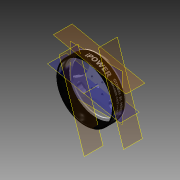
# Autodesk Inventor part: end_bell
Saved by Autodesk Inventor 2013 (Build 170138000, 138)
## iProperties
Created: 2013-09-27
Part Number: end_bell
Material: Generic
Document SubType Name: Modeling
Designer: Hunter
Density: 1 g/cm^3
Author: Hunter
Autodesk Inventor part; units mm, degrees
(part 1 of 2)
ref_plane "YZ Plane" through (0, 0, 0) normal (1, 0, 0) x (0, 1, 0)
ref_plane "XZ Plane" through (0, 0, 0) normal (0, 1, 0) x (-1, 0, 0)
ref_plane "XY Plane" through (0, 0, 0) normal (0, 0, 1) x (1, 0, 0)
sketch "Sketch1" plane through (0, 0, 0) normal (0, 1, 0) x (-1, 0, 0)
  circle A0 centre (0, 0) radius 25
  circle A1 centre (0, 0) radius 1.585
  circle A2 centre (0, 16) radius 4
  circle A3 centre (-13.8564, -8) radius 4
  circle A4 centre (13.8564, -8) radius 4
  line L0 (0, 0) -> (19.669, 0) construction
  line L1 (0, 0) -> (0, 10.3871) construction
  line L2 (-4.2426, -4.2426) -> (4.2426, -4.2426) construction
  line L3 (4.2426, -4.2426) -> (4.2426, 4.2426) construction
  line L4 (4.2426, 4.2426) -> (-4.2426, 4.2426) construction
  line L5 (-4.2426, 4.2426) -> (-4.2426, -4.2426) construction
  circle A5 centre (-4.2426, 4.2426) radius 1
  circle A6 centre (4.2426, 4.2426) radius 1
  circle A7 centre (-4.2426, -4.2426) radius 1
  circle A8 centre (4.2426, -4.2426) radius 1
  line L6 (-4.2426, 4.2426) -> (4.2426, -4.2426) construction
  dimension "d0" = 50
  dimension "d1" = 3.17
  dimension "d2" = 8
  dimension "d3" = 16
  dimension "d6" = 360
  dimension "d10" = 2
  dimension "d11" = 2
  dimension "d12" = 2
  dimension "d13" = 2
  dimension "d86" = 12
  constraints: 14 end point, 9 centre point, 6 coincident, 3 horizontal, 2 parallel, 2 perpendicular, 9 other
  measures "d0" diameter of A0
  measures "d1" diameter of A1
  measures "d2" diameter of A2
  measures "d3" distance of L0.start A2.centre
  measures "d10" diameter of A5
  measures "d11" diameter of A6
  measures "d12" diameter of A7
  measures "d13" diameter of A8
  measures "d86" distance of L6.start L6.end
extrude "Extrusion1" add sketch "Sketch1" along normal blind 15
sketch "Sketch2" plane through (0, 15, 0) normal (0, 1, 0) x (1, 0, 0)
  circle A0 centre (13.8564, 8) radius 4 projected
  circle A1 centre (0, -16) radius 4 projected
  circle A2 centre (0, 0) radius 1.585 projected
  circle A3 centre (0, 0) radius 25 projected
  line L0 (0, 0) -> (46.4699, 0) construction
  circle A4 centre (0, 32.1597) radius 21.3512
  circle A5 centre (-27.8511, -16.0798) radius 21.3512
  circle A6 centre (27.8511, -16.0798) radius 21.3512
  circle A7 centre (0, -16) radius 6.5 construction
  circle A8 centre (13.8564, 8) radius 6.5 construction
  dimension "d19" = 360
  dimension "d21" = 13
  dimension "d22" = 13
  constraints: 5 centre point, 2 coincident, 2 end point, 1 horizontal, 1 tangent, 7 other
  measures "d21" diameter of A7
  measures "d22" diameter of A8
extrude "Extrusion2" cut sketch "Sketch2" against normal blind 4 contours A3 A6 | A3 A6 | A4 A3 | A3 A4 | A5 A3 | A3 A5
chamfer "Chamfer1" distance 4 angle 45 1 edges at (-21.6506, 15, -12.5)
chamfer "Chamfer2" distance 4 angle 45 2 edges at (21.6506, 15, -12.5) (0, 15, 25)
sketch "Sketch3" plane through (0, 0, 0) normal (0, -1, 0) x (1, 0, 0)
  circle A0 centre (-13.8564, -8) radius 4 projected
  circle A1 centre (13.8564, -8) radius 4 projected
  circle A2 centre (0, 16) radius 4 projected
  circle A3 centre (0, 0) radius 1.585 projected
  circle A4 centre (-4.2426, -4.2426) radius 1 projected
  circle A5 centre (4.2426, -4.2426) radius 1 projected
  circle A6 centre (-4.2426, 4.2426) radius 1 projected
  circle A7 centre (4.2426, 4.2426) radius 1 projected
  circle A8 centre (0, 0) radius 25 projected
  circle A9 centre (0, 0) radius 23.7
  dimension "d31" = 1.3
  constraints: 1 centre point, 1 coincident
  measures "d31" radial gap between concentric circles of A8 A9
extrude "Extrusion3" cut sketch "Sketch3" against normal blind 10 contours A9
sketch "Sketch4" plane through (0, 10, 0) normal (0, -1, 0) x (1, 0, 0)
  circle A0 centre (0, 16) radius 4 projected
  circle A1 centre (13.8564, -8) radius 4 projected
  circle A2 centre (-13.8564, -8) radius 4 projected
  circle A3 centre (0, 0) radius 1.585 projected
  circle A4 centre (4.2426, 4.2426) radius 1 projected
  circle A5 centre (-4.2426, 4.2426) radius 1 projected
  circle A6 centre (4.2426, -4.2426) radius 1 projected
  circle A7 centre (-4.2426, -4.2426) radius 1 projected
  circle A8 centre (0, 0) radius 23.7 projected
  circle A9 centre (0, 0) radius 21.7
  dimension "d34" = 43.4
  constraints: 1 centre point, 1 coincident
  measures "d34" diameter of A9
extrude "Extrusion4" cut sketch "Sketch4" against normal blind 1 contours A9
hole "Hole1" at (-4.2426, 15, 4.2426) direction (0, -1, 0) diameter 2.013 end through all thread size "M2.5x0.45" class "6H" standard "ANSI Metric M Profile"
hole "Hole2" at (-4.2426, 15, -4.2426) direction (0, -1, 0) diameter 2.013 end through all thread size "M2.5x0.45" class "6H" standard "ANSI Metric M Profile"
hole "Hole3" at (4.2426, 15, -4.2426) direction (0, -1, 0) diameter 2.013 end through all thread size "M2.5x0.45" class "6H" standard "ANSI Metric M Profile"
hole "Hole4" at (4.2426, 15, 4.2426) direction (0, -1, 0) diameter 2.013 end through all thread size "M2.5x0.45" class "6H" standard "ANSI Metric M Profile"
chamfer "Chamfer3" distance 0.1 angle 45 4 edges at (-4.2426, 15, -5.2491) (-4.2426, 15, 3.2361) (4.2426, 15, 3.2361) (4.2426, 15, -5.2491)
ref_plane "Work Plane1" through (0, 10, 0) normal (0, 1, 0) x (1, 0, 0)
split body "Split1" result two bodies by plane through (0, 10, 0) normal (0, 1, 0) first body at (-7.4399, 11.5, 0.4135)
fillet "Fillet1" radius 0.3 1 edges at (25, 0, 0)
fillet "Fillet2" radius 0.3 1 edges at (-23.7, 0, 0)
ref_plane "Work Plane2" through (0, 0, 0) normal (0.9488702, 0, 0.3156666) x (0, 1, 0)
ref_plane "Work Plane3" through (23.7218, 0, 7.8917) normal (0.9488702, 0, 0.3156666) x (0, 1, 0)
sketch "Sketch5" plane through (23.7218, 0, 7.8917) normal (0.9488702, 0, 0.3156666) x (0, 1, 0)
  line L0 (-5.6648, 40.291) -> (1.694, 40.291)
  line L1 (1.694, 40.291) -> (1.694, -6.6562)
  line L2 (1.694, -6.6562) -> (-5.6648, -6.6562)
  line L3 (-5.6648, -6.6562) -> (-5.6648, 40.291)
  line L4 (7.9505, 10.1086) -> (7.9505, -71.0946) construction
  line L5 (7.9505, -71.0946) -> (-7.0524, -71.0946) construction
  line L6 (-7.0524, -71.0946) -> (-7.0524, 10.1086) construction
  line L7 (-7.0524, 10.1086) -> (7.9505, 10.1086) construction
  spline S0 degree 2 poles (6.0218, 8.2317) (5.9683, 8.363) (5.8662, 8.7828) (5.8662, 8.987) knots 0 0 0 1 2 2 2
  spline S1 degree 2 poles (5.8662, 8.987) (5.8662, 9.4586) (6.4108, 10.0178) (6.91, 10.0178) knots 0 0 0 1 2 2 2
  spline S2 degree 2 poles (6.91, 10.0178) (7.38, 10.0178) (7.9472, 9.4586) (7.9472, 8.9724) knots 0 0 0 1 2 2 2
  spline S3 degree 2 poles (7.9472, 8.9724) (7.9472, 8.7212) (7.8516, 8.4068) (7.7706, 8.2398) knots 0 0 0 1 2 2 2
  line L8 (7.7706, 8.2398) -> (7.3006, 8.2398)
  line L9 (7.3006, 8.2398) -> (7.3006, 8.2852)
  spline S4 degree 2 poles (7.3006, 8.2852) (7.3281, 8.3209) (7.4335, 8.457) (7.4691, 8.5218) knots 0 0 0 1 2 2 2
  spline S5 degree 2 poles (7.4691, 8.5218) (7.5129, 8.5964) (7.5745, 8.7941) (7.5745, 8.9043) knots 0 0 0 1 2 2 2
  spline S6 degree 2 poles (7.5745, 8.9043) (7.5745, 9.0324) (7.4934, 9.2447) (7.4108, 9.3274) knots 0 0 0 1 2 2 2
  spline S7 degree 2 poles (7.4108, 9.3274) (7.3297, 9.4068) (7.0818, 9.4992) (6.9181, 9.4992) knots 0 0 0 1 2 2 2
  spline S8 degree 2 poles (6.9181, 9.4992) (6.568, 9.4992) (6.2341, 9.1475) (6.2341, 8.8444) knots 0 0 0 1 2 2 2
  spline S9 degree 2 poles (6.2341, 8.8444) (6.2341, 8.8168) (6.2374, 8.7455) (6.239, 8.718) knots 0 0 0 1 2 2 2
  line L10 (6.239, 8.718) -> (6.6328, 8.718)
  line L11 (6.6328, 8.718) -> (6.6328, 9.1053)
  line L12 (6.6328, 9.1053) -> (7.0072, 9.1053)
  line L13 (7.0072, 9.1053) -> (7.0072, 8.2317)
  line L14 (7.0072, 8.2317) -> (6.0218, 8.2317)
  line L15 (5.9083, 6.8573) -> (5.9083, 7.9335)
  line L16 (5.9083, 7.9335) -> (6.2568, 7.9335)
  line L17 (6.2568, 7.9335) -> (6.2568, 7.6466)
  line L18 (6.2568, 7.6466) -> (7.5599, 7.6466)
  line L19 (7.5599, 7.6466) -> (7.5599, 7.9335)
  line L20 (7.5599, 7.9335) -> (7.9083, 7.9335)
  line L21 (7.9083, 7.9335) -> (7.9083, 6.8573)
  line L22 (7.9083, 6.8573) -> (7.5599, 6.8573)
  line L23 (7.5599, 6.8573) -> (7.5599, 7.1442)
  line L24 (7.5599, 7.1442) -> (6.2568, 7.1442)
  line L25 (6.2568, 7.1442) -> (6.2568, 6.8573)
  line L26 (6.2568, 6.8573) -> (5.9083, 6.8573)
  line L27 (5.9083, 4.4813) -> (5.9083, 4.9805)
  line L28 (5.9083, 4.9805) -> (7.2341, 4.9805)
  line L29 (7.2341, 4.9805) -> (6.3784, 5.3436)
  line L30 (6.3784, 5.3436) -> (6.3784, 5.6872)
  line L31 (6.3784, 5.6872) -> (7.2341, 6.0502)
  line L32 (7.2341, 6.0502) -> (5.9083, 6.0502)
  line L33 (5.9083, 6.0502) -> (5.9083, 6.5235)
  line L34 (5.9083, 6.5235) -> (7.9083, 6.5235)
  line L35 (7.9083, 6.5235) -> (7.9083, 5.9449)
  line L36 (7.9083, 5.9449) -> (6.9213, 5.5008)
  line L37 (6.9213, 5.5008) -> (7.9083, 5.0599)
  line L38 (7.9083, 5.0599) -> (7.9083, 4.4813)
  line L39 (7.9083, 4.4813) -> (5.9083, 4.4813)
  spline S10 degree 2 poles (6.521, 2.4684) (6.3719, 2.4684) (6.1466, 2.5818) (6.072, 2.6758) knots 0 0 0 1 2 2 2
  spline S11 degree 2 poles (6.072, 2.6758) (5.9829, 2.7893) (5.9083, 3.0583) (5.9083, 3.2674) knots 0 0 0 1 2 2 2
  line L40 (5.9083, 3.2674) -> (5.9083, 4.0664)
  line L41 (5.9083, 4.0664) -> (7.9083, 4.0664)
  line L42 (7.9083, 4.0664) -> (7.9083, 3.3614)
  spline S12 degree 2 poles (7.9083, 3.3614) (7.9083, 3.141) (7.8743, 2.9141) (7.8208, 2.8152) knots 0 0 0 1 2 2 2
  spline S13 degree 2 poles (7.8208, 2.8152) (7.7641, 2.7066) (7.5696, 2.6013) (7.4432, 2.6013) knots 0 0 0 1 2 2 2
  spline S14 degree 2 poles (7.4432, 2.6013) (7.2973, 2.6013) (7.0688, 2.7471) (7.0153, 2.8768) knots 0 0 0 1 2 2 2
  line L43 (7.0153, 2.8768) -> (7.0056, 2.8768)
  spline S15 degree 2 poles (7.0056, 2.8768) (6.9667, 2.6904) (6.7252, 2.4684) (6.521, 2.4684) knots 0 0 0 1 2 2 2
  spline S16 degree 2 poles (6.5291, 2.987) (6.6231, 2.987) (6.7284, 3.0616) (6.756, 3.1361) knots 0 0 0 1 2 2 2
  spline S17 degree 2 poles (6.756, 3.1361) (6.7738, 3.1815) (6.7771, 3.3419) (6.7771, 3.4748) knots 0 0 0 1 2 2 2
  line L44 (6.7771, 3.4748) -> (6.7771, 3.5672)
  line L45 (6.7771, 3.5672) -> (6.273, 3.5672)
  line L46 (6.273, 3.5672) -> (6.273, 3.5397)
  spline S18 degree 2 poles (6.273, 3.5397) (6.273, 3.3452) (6.2779, 3.1961) (6.3119, 3.1183) knots 0 0 0 1 2 2 2
  spline S19 degree 2 poles (6.3119, 3.1183) (6.3427, 3.0502) (6.4562, 2.987) (6.5291, 2.987) knots 0 0 0 1 2 2 2
  spline S20 degree 2 poles (7.3443, 3.1118) (7.3929, 3.1118) (7.4951, 3.162) (7.5177, 3.2139) knots 0 0 0 1 2 2 2
  spline S21 degree 2 poles (7.5177, 3.2139) (7.5404, 3.2625) (7.5437, 3.3987) (7.5437, 3.5332) knots 0 0 0 1 2 2 2
  line L47 (7.5437, 3.5332) -> (7.5437, 3.5672)
  line L48 (7.5437, 3.5672) -> (7.119, 3.5672)
  line L49 (7.119, 3.5672) -> (7.119, 3.504)
  spline S22 degree 2 poles (7.119, 3.504) (7.119, 3.376) (7.1239, 3.2723) (7.1498, 3.2171) knots 0 0 0 1 2 2 2
  spline S23 degree 2 poles (7.1498, 3.2171) (7.179, 3.1572) (7.2779, 3.1118) (7.3443, 3.1118) knots 0 0 0 1 2 2 2
  line L50 (5.9083, 2.3954) -> (7.9083, 1.7196)
  line L51 (7.9083, 1.7196) -> (7.9083, 1.1718)
  line L52 (7.9083, 1.1718) -> (5.9083, 0.4959)
  line L53 (5.9083, 0.4959) -> (5.9083, 1.0129)
  line L54 (5.9083, 1.0129) -> (6.3168, 1.1377)
  line L55 (6.3168, 1.1377) -> (6.3168, 1.7666)
  line L56 (6.3168, 1.7666) -> (5.9083, 1.893)
  line L57 (5.9083, 1.893) -> (5.9083, 2.3954)
  line L58 (6.6798, 1.2479) -> (7.3411, 1.4522)
  line L59 (7.3411, 1.4522) -> (6.6798, 1.658)
  line L60 (6.6798, 1.658) -> (6.6798, 1.2479)
  line L61 (5.9083, -1.0373) -> (5.9083, 0.2966)
  line L62 (5.9083, 0.2966) -> (7.9083, 0.2966)
  line L63 (7.9083, 0.2966) -> (7.9083, -0.2059)
  line L64 (7.9083, -0.2059) -> (6.2892, -0.2059)
  line L65 (6.2892, -0.2059) -> (6.2892, -1.0373)
  line L66 (6.2892, -1.0373) -> (5.9083, -1.0373)
  spline S24 degree 2 poles (6.521, -3.6807) (6.3719, -3.6807) (6.1466, -3.5673) (6.072, -3.4733) knots 0 0 0 1 2 2 2
  spline S25 degree 2 poles (6.072, -3.4733) (5.9829, -3.3598) (5.9083, -3.0908) (5.9083, -2.8817) knots 0 0 0 1 2 2 2
  line L67 (5.9083, -2.8817) -> (5.9083, -2.0827)
  line L68 (5.9083, -2.0827) -> (7.9083, -2.0827)
  line L69 (7.9083, -2.0827) -> (7.9083, -2.7877)
  spline S26 degree 2 poles (7.9083, -2.7877) (7.9083, -3.0081) (7.8743, -3.235) (7.8208, -3.3339) knots 0 0 0 1 2 2 2
  spline S27 degree 2 poles (7.8208, -3.3339) (7.7641, -3.4425) (7.5696, -3.5478) (7.4432, -3.5478) knots 0 0 0 1 2 2 2
  spline S28 degree 2 poles (7.4432, -3.5478) (7.2973, -3.5478) (7.0688, -3.402) (7.0153, -3.2723) knots 0 0 0 1 2 2 2
  line L70 (7.0153, -3.2723) -> (7.0056, -3.2723)
  spline S29 degree 2 poles (7.0056, -3.2723) (6.9667, -3.4587) (6.7252, -3.6807) (6.521, -3.6807) knots 0 0 0 1 2 2 2
  spline S30 degree 2 poles (6.5291, -3.1621) (6.6231, -3.1621) (6.7284, -3.0876) (6.756, -3.013) knots 0 0 0 1 2 2 2
  spline S31 degree 2 poles (6.756, -3.013) (6.7738, -2.9676) (6.7771, -2.8072) (6.7771, -2.6743) knots 0 0 0 1 2 2 2
  line L71 (6.7771, -2.6743) -> (6.7771, -2.5819)
  line L72 (6.7771, -2.5819) -> (6.273, -2.5819)
  line L73 (6.273, -2.5819) -> (6.273, -2.6094)
  spline S32 degree 2 poles (6.273, -2.6094) (6.273, -2.8039) (6.2779, -2.953) (6.3119, -3.0308) knots 0 0 0 1 2 2 2
  spline S33 degree 2 poles (6.3119, -3.0308) (6.3427, -3.0989) (6.4562, -3.1621) (6.5291, -3.1621) knots 0 0 0 1 2 2 2
  spline S34 degree 2 poles (7.3443, -3.0373) (7.3929, -3.0373) (7.4951, -2.9871) (7.5177, -2.9352) knots 0 0 0 1 2 2 2
  spline S35 degree 2 poles (7.5177, -2.9352) (7.5404, -2.8866) (7.5437, -2.7504) (7.5437, -2.6159) knots 0 0 0 1 2 2 2
  line L74 (7.5437, -2.6159) -> (7.5437, -2.5819)
  line L75 (7.5437, -2.5819) -> (7.119, -2.5819)
  line L76 (7.119, -2.5819) -> (7.119, -2.6451)
  spline S36 degree 2 poles (7.119, -2.6451) (7.119, -2.7731) (7.1239, -2.8769) (7.1498, -2.932) knots 0 0 0 1 2 2 2
  spline S37 degree 2 poles (7.1498, -2.932) (7.179, -2.9919) (7.2779, -3.0373) (7.3443, -3.0373) knots 0 0 0 1 2 2 2
  line L77 (5.9083, -5.3031) -> (5.9083, -3.9692)
  line L78 (5.9083, -3.9692) -> (7.9083, -3.9692)
  line L79 (7.9083, -3.9692) -> (7.9083, -4.4717)
  line L80 (7.9083, -4.4717) -> (6.2892, -4.4717)
  line L81 (6.2892, -4.4717) -> (6.2892, -5.3031)
  line L82 (6.2892, -5.3031) -> (5.9083, -5.3031)
  line L83 (5.9083, -8.3906) -> (5.9083, -7.8914)
  line L84 (5.9083, -7.8914) -> (7.2341, -7.8914)
  line L85 (7.2341, -7.8914) -> (6.3784, -7.5284)
  line L86 (6.3784, -7.5284) -> (6.3784, -7.1848)
  line L87 (6.3784, -7.1848) -> (7.2341, -6.8218)
  line L88 (7.2341, -6.8218) -> (5.9083, -6.8218)
  line L89 (5.9083, -6.8218) -> (5.9083, -6.3485)
  line L90 (5.9083, -6.3485) -> (7.9083, -6.3485)
  line L91 (7.9083, -6.3485) -> (7.9083, -6.9271)
  line L92 (7.9083, -6.9271) -> (6.9213, -7.3712)
  line L93 (6.9213, -7.3712) -> (7.9083, -7.812)
  line L94 (7.9083, -7.812) -> (7.9083, -8.3906)
  line L95 (7.9083, -8.3906) -> (5.9083, -8.3906)
  spline S38 degree 2 poles (6.9083, -10.6256) (6.4221, -10.6256) (5.8662, -10.107) (5.8662, -9.6564) knots 0 0 0 1 2 2 2
  spline S39 degree 2 poles (5.8662, -9.6564) (5.8662, -9.2042) (6.4286, -8.6888) (6.9083, -8.6888) knots 0 0 0 1 2 2 2
  spline S40 degree 2 poles (6.9083, -8.6888) (7.3897, -8.6888) (7.9505, -9.2042) (7.9505, -9.6564) knots 0 0 0 1 2 2 2
  spline S41 degree 2 poles (7.9505, -9.6564) (7.9505, -10.107) (7.3929, -10.6256) (6.9083, -10.6256) knots 0 0 0 1 2 2 2
  spline S42 degree 2 poles (6.9083, -10.107) (7.0882, -10.107) (7.3395, -10.0341) (7.4189, -9.9709) knots 0 0 0 1 2 2 2
  spline S43 degree 2 poles (7.4189, -9.9709) (7.5015, -9.9076) (7.5729, -9.7456) (7.5729, -9.6581) knots 0 0 0 1 2 2 2
  spline S44 degree 2 poles (7.5729, -9.6581) (7.5729, -9.5657) (7.5064, -9.4149) (7.4221, -9.3453) knots 0 0 0 1 2 2 2
  spline S45 degree 2 poles (7.4221, -9.3453) (7.3443, -9.2837) (7.0866, -9.2075) (6.9083, -9.2075) knots 0 0 0 1 2 2 2
  spline S46 degree 2 poles (6.9083, -9.2075) (6.7236, -9.2075) (6.4805, -9.2804) (6.3978, -9.3436) knots 0 0 0 1 2 2 2
  spline S47 degree 2 poles (6.3978, -9.3436) (6.3152, -9.4068) (6.2438, -9.5705) (6.2438, -9.6581) knots 0 0 0 1 2 2 2
  spline S48 degree 2 poles (6.2438, -9.6581) (6.2438, -9.7472) (6.32, -9.9125) (6.4011, -9.9725) knots 0 0 0 1 2 2 2
  spline S49 degree 2 poles (6.4011, -9.9725) (6.4886, -10.0373) (6.7203, -10.107) (6.9083, -10.107) knots 0 0 0 1 2 2 2
  line L96 (5.9083, -11.308) -> (7.5275, -11.308)
  line L97 (7.5275, -11.308) -> (7.5275, -10.7164)
  line L98 (7.5275, -10.7164) -> (7.9083, -10.7164)
  line L99 (7.9083, -10.7164) -> (7.9083, -12.402)
  line L100 (7.9083, -12.402) -> (7.5275, -12.402)
  line L101 (7.5275, -12.402) -> (7.5275, -11.8104)
  line L102 (7.5275, -11.8104) -> (5.9083, -11.8104)
  line L103 (5.9083, -11.8104) -> (5.9083, -11.308)
  spline S50 degree 2 poles (6.9083, -14.4279) (6.4221, -14.4279) (5.8662, -13.9093) (5.8662, -13.4587) knots 0 0 0 1 2 2 2
  spline S51 degree 2 poles (5.8662, -13.4587) (5.8662, -13.0065) (6.4286, -12.4911) (6.9083, -12.4911) knots 0 0 0 1 2 2 2
  spline S52 degree 2 poles (6.9083, -12.4911) (7.3897, -12.4911) (7.9505, -13.0065) (7.9505, -13.4587) knots 0 0 0 1 2 2 2
  spline S53 degree 2 poles (7.9505, -13.4587) (7.9505, -13.9093) (7.3929, -14.4279) (6.9083, -14.4279) knots 0 0 0 1 2 2 2
  spline S54 degree 2 poles (6.9083, -13.9093) (7.0882, -13.9093) (7.3395, -13.8363) (7.4189, -13.7731) knots 0 0 0 1 2 2 2
  spline S55 degree 2 poles (7.4189, -13.7731) (7.5015, -13.7099) (7.5729, -13.5478) (7.5729, -13.4603) knots 0 0 0 1 2 2 2
  spline S56 degree 2 poles (7.5729, -13.4603) (7.5729, -13.3679) (7.5064, -13.2172) (7.4221, -13.1475) knots 0 0 0 1 2 2 2
  spline S57 degree 2 poles (7.4221, -13.1475) (7.3443, -13.0859) (7.0866, -13.0098) (6.9083, -13.0098) knots 0 0 0 1 2 2 2
  spline S58 degree 2 poles (6.9083, -13.0098) (6.7236, -13.0098) (6.4805, -13.0827) (6.3978, -13.1459) knots 0 0 0 1 2 2 2
  spline S59 degree 2 poles (6.3978, -13.1459) (6.3152, -13.2091) (6.2438, -13.3728) (6.2438, -13.4603) knots 0 0 0 1 2 2 2
  spline S60 degree 2 poles (6.2438, -13.4603) (6.2438, -13.5495) (6.32, -13.7148) (6.4011, -13.7747) knots 0 0 0 1 2 2 2
  spline S61 degree 2 poles (6.4011, -13.7747) (6.4886, -13.8396) (6.7203, -13.9093) (6.9083, -13.9093) knots 0 0 0 1 2 2 2
  line L104 (5.9083, -16.5738) -> (5.9083, -15.9628)
  line L105 (5.9083, -15.9628) -> (6.6425, -15.4068)
  line L106 (6.6425, -15.4068) -> (6.6425, -15.2253)
  line L107 (6.6425, -15.2253) -> (5.9083, -15.2253)
  line L108 (5.9083, -15.2253) -> (5.9083, -14.7261)
  line L109 (5.9083, -14.7261) -> (7.9083, -14.7261)
  line L110 (7.9083, -14.7261) -> (7.9083, -15.53)
  spline S62 degree 2 poles (7.9083, -15.53) (7.9083, -15.697) (7.8662, -15.9433) (7.8014, -16.0487) knots 0 0 0 1 2 2 2
  spline S63 degree 2 poles (7.8014, -16.0487) (7.7333, -16.1556) (7.521, -16.282) (7.3589, -16.282) knots 0 0 0 1 2 2 2
  spline S64 degree 2 poles (7.3589, -16.282) (7.1304, -16.282) (6.8435, -16.0746) (6.7592, -15.9012) knots 0 0 0 1 2 2 2
  line L111 (6.7592, -15.9012) -> (5.9083, -16.5738)
  spline S65 degree 2 poles (7.2957, -15.7666) (7.3719, -15.7666) (7.4805, -15.7083) (7.5096, -15.6418) knots 0 0 0 1 2 2 2
  spline S66 degree 2 poles (7.5096, -15.6418) (7.5291, -15.5948) (7.5404, -15.4798) (7.5404, -15.3939) knots 0 0 0 1 2 2 2
  line L112 (7.5404, -15.3939) -> (7.5404, -15.2253)
  line L113 (7.5404, -15.2253) -> (7.0023, -15.2253)
  line L114 (7.0023, -15.2253) -> (7.0023, -15.3696)
  spline S67 degree 2 poles (7.0023, -15.3696) (7.0023, -15.4733) (7.0283, -15.6208) (7.0688, -15.671) knots 0 0 0 1 2 2 2
  spline S68 degree 2 poles (7.0688, -15.671) (7.1077, -15.7196) (7.2114, -15.7666) (7.2957, -15.7666) knots 0 0 0 1 2 2 2
  spline S69 degree 2 poles (3.2942, 8.7009) (3.2541, 8.7994) (3.1775, 9.1142) (3.1775, 9.2674) knots 0 0 0 1 2 2 2
  spline S70 degree 2 poles (3.1775, 9.2674) (3.1775, 9.6211) (3.5859, 10.0405) (3.9603, 10.0405) knots 0 0 0 1 2 2 2
  spline S71 degree 2 poles (3.9603, 10.0405) (4.3128, 10.0405) (4.7383, 9.6211) (4.7383, 9.2565) knots 0 0 0 1 2 2 2
  spline S72 degree 2 poles (4.7383, 9.2565) (4.7383, 9.068) (4.6665, 8.8322) (4.6058, 8.707) knots 0 0 0 1 2 2 2
  line L115 (4.6058, 8.707) -> (4.2533, 8.707)
  line L116 (4.2533, 8.707) -> (4.2533, 8.7411)
  spline S73 degree 2 poles (4.2533, 8.7411) (4.2739, 8.7678) (4.3529, 8.8699) (4.3797, 8.9185) knots 0 0 0 1 2 2 2
  spline S74 degree 2 poles (4.3797, 8.9185) (4.4125, 8.9744) (4.4587, 9.1227) (4.4587, 9.2054) knots 0 0 0 1 2 2 2
  spline S75 degree 2 poles (4.4587, 9.2054) (4.4587, 9.3014) (4.3979, 9.4607) (4.3359, 9.5227) knots 0 0 0 1 2 2 2
  spline S76 degree 2 poles (4.3359, 9.5227) (4.2751, 9.5822) (4.0892, 9.6515) (3.9664, 9.6515) knots 0 0 0 1 2 2 2
  spline S77 degree 2 poles (3.9664, 9.6515) (3.7038, 9.6515) (3.4534, 9.3877) (3.4534, 9.1604) knots 0 0 0 1 2 2 2
  spline S78 degree 2 poles (3.4534, 9.1604) (3.4534, 9.1398) (3.4558, 9.0863) (3.4571, 9.0656) knots 0 0 0 1 2 2 2
  line L117 (3.4571, 9.0656) -> (3.7524, 9.0656)
  line L118 (3.7524, 9.0656) -> (3.7524, 9.3561)
  line L119 (3.7524, 9.3561) -> (4.0332, 9.3561)
  line L120 (4.0332, 9.3561) -> (4.0332, 8.7009)
  line L121 (4.0332, 8.7009) -> (3.2942, 8.7009)
  spline S79 degree 2 poles (3.6686, 7.218) (3.5567, 7.218) (3.3878, 7.303) (3.3319, 7.3735) knots 0 0 0 1 2 2 2
  spline S80 degree 2 poles (3.3319, 7.3735) (3.265, 7.4586) (3.2091, 7.6604) (3.2091, 7.8172) knots 0 0 0 1 2 2 2
  line L122 (3.2091, 7.8172) -> (3.2091, 8.4165)
  line L123 (3.2091, 8.4165) -> (4.7091, 8.4165)
  line L124 (4.7091, 8.4165) -> (4.7091, 7.8877)
  spline S81 degree 2 poles (4.7091, 7.8877) (4.7091, 7.7224) (4.6836, 7.5522) (4.6434, 7.4781) knots 0 0 0 1 2 2 2
  spline S82 degree 2 poles (4.6434, 7.4781) (4.6009, 7.3966) (4.455, 7.3176) (4.3602, 7.3176) knots 0 0 0 1 2 2 2
  spline S83 degree 2 poles (4.3602, 7.3176) (4.2508, 7.3176) (4.0794, 7.427) (4.0393, 7.5243) knots 0 0 0 1 2 2 2
  line L125 (4.0393, 7.5243) -> (4.032, 7.5243)
  spline S84 degree 2 poles (4.032, 7.5243) (4.0028, 7.3845) (3.8217, 7.218) (3.6686, 7.218) knots 0 0 0 1 2 2 2
  spline S85 degree 2 poles (3.6746, 7.6069) (3.7451, 7.6069) (3.8242, 7.6629) (3.8448, 7.7188) knots 0 0 0 1 2 2 2
  spline S86 degree 2 poles (3.8448, 7.7188) (3.8582, 7.7528) (3.8606, 7.8731) (3.8606, 7.9728) knots 0 0 0 1 2 2 2
  line L126 (3.8606, 7.9728) -> (3.8606, 8.0421)
  line L127 (3.8606, 8.0421) -> (3.4826, 8.0421)
  line L128 (3.4826, 8.0421) -> (3.4826, 8.0214)
  spline S87 degree 2 poles (3.4826, 8.0214) (3.4826, 7.8756) (3.4862, 7.7637) (3.5118, 7.7054) knots 0 0 0 1 2 2 2
  spline S88 degree 2 poles (3.5118, 7.7054) (3.5349, 7.6543) (3.6199, 7.6069) (3.6746, 7.6069) knots 0 0 0 1 2 2 2
  spline S89 degree 2 poles (4.2861, 7.7005) (4.3225, 7.7005) (4.3991, 7.7382) (4.4161, 7.7771) knots 0 0 0 1 2 2 2
  spline S90 degree 2 poles (4.4161, 7.7771) (4.4332, 7.8136) (4.4356, 7.9157) (4.4356, 8.0166) knots 0 0 0 1 2 2 2
  line L129 (4.4356, 8.0166) -> (4.4356, 8.0421)
  line L130 (4.4356, 8.0421) -> (4.1171, 8.0421)
  line L131 (4.1171, 8.0421) -> (4.1171, 7.9947)
  spline S91 degree 2 poles (4.1171, 7.9947) (4.1171, 7.8987) (4.1208, 7.8209) (4.1402, 7.7795) knots 0 0 0 1 2 2 2
  spline S92 degree 2 poles (4.1402, 7.7795) (4.1621, 7.7346) (4.2362, 7.7005) (4.2861, 7.7005) knots 0 0 0 1 2 2 2
  line L132 (3.2091, 5.47) -> (3.2091, 5.8444)
  line L133 (3.2091, 5.8444) -> (4.2034, 5.8444)
  line L134 (4.2034, 5.8444) -> (3.5616, 6.1167)
  line L135 (3.5616, 6.1167) -> (3.5616, 6.3744)
  line L136 (3.5616, 6.3744) -> (4.2034, 6.6466)
  line L137 (4.2034, 6.6466) -> (3.2091, 6.6466)
  line L138 (3.2091, 6.6466) -> (3.2091, 7.0016)
  line L139 (3.2091, 7.0016) -> (4.7091, 7.0016)
  line L140 (4.7091, 7.0016) -> (4.7091, 6.5676)
  line L141 (4.7091, 6.5676) -> (3.9688, 6.2346)
  line L142 (3.9688, 6.2346) -> (4.7091, 5.9039)
  line L143 (4.7091, 5.9039) -> (4.7091, 5.47)
  line L144 (4.7091, 5.47) -> (3.2091, 5.47)
  line L145 (3.5592, 4.0417) -> (3.5592, 4.2447)
  line L146 (3.5592, 4.2447) -> (3.2054, 4.2447)
  line L147 (3.2054, 4.2447) -> (3.2054, 4.6082)
  line L148 (3.2054, 4.6082) -> (3.5592, 4.6082)
  line L149 (3.5592, 4.6082) -> (3.5592, 5.2694)
  line L150 (3.5592, 5.2694) -> (3.8387, 5.2694)
  line L151 (3.8387, 5.2694) -> (4.7091, 4.6203)
  line L152 (4.7091, 4.6203) -> (4.7091, 4.2447)
  line L153 (4.7091, 4.2447) -> (3.829, 4.2447)
  line L154 (3.829, 4.2447) -> (3.829, 4.0417)
  line L155 (3.829, 4.0417) -> (3.5592, 4.0417)
  line L156 (3.829, 4.6082) -> (4.3396, 4.6082)
  line L157 (4.3396, 4.6082) -> (3.829, 4.9886)
  line L158 (3.829, 4.9886) -> (3.829, 4.6082)
  spline S93 degree 2 poles (3.9591, 2.7654) (3.7646, 2.7654) (3.4729, 2.8274) (3.3744, 2.8966) knots 0 0 0 1 2 2 2
  spline S94 degree 2 poles (3.3744, 2.8966) (3.2772, 2.9647) (3.1775, 3.1847) (3.1775, 3.3428) knots 0 0 0 1 2 2 2
  spline S95 degree 2 poles (3.1775, 3.3428) (3.1775, 3.502) (3.2772, 3.7208) (3.3768, 3.7901) knots 0 0 0 1 2 2 2
  spline S96 degree 2 poles (3.3768, 3.7901) (3.4753, 3.8594) (3.7646, 3.9214) (3.9591, 3.9214) knots 0 0 0 1 2 2 2
  spline S97 degree 2 poles (3.9591, 3.9214) (4.1584, 3.9214) (4.4404, 3.8594) (4.5426, 3.7889) knots 0 0 0 1 2 2 2
  spline S98 degree 2 poles (4.5426, 3.7889) (4.6422, 3.7184) (4.7395, 3.4959) (4.7395, 3.3428) knots 0 0 0 1 2 2 2
  spline S99 degree 2 poles (4.7395, 3.3428) (4.7395, 3.1811) (4.6374, 2.9647) (4.5365, 2.8954) knots 0 0 0 1 2 2 2
  spline S100 degree 2 poles (4.5365, 2.8954) (4.438, 2.8274) (4.1475, 2.7654) (3.9591, 2.7654) knots 0 0 0 1 2 2 2
  spline S101 degree 2 poles (3.9591, 3.1434) (4.2375, 3.1434) (4.4623, 3.2346) (4.4623, 3.3428) knots 0 0 0 1 2 2 2
  spline S102 degree 2 poles (4.4623, 3.3428) (4.4623, 3.4509) (4.2375, 3.5433) (3.9579, 3.5433) knots 0 0 0 1 2 2 2
  spline S103 degree 2 poles (3.9579, 3.5433) (3.6832, 3.5433) (3.4546, 3.4509) (3.4546, 3.3428) knots 0 0 0 1 2 2 2
  spline S104 degree 2 poles (3.4546, 3.3428) (3.4546, 3.2358) (3.6832, 3.1434) (3.9591, 3.1434) knots 0 0 0 1 2 2 2
  spline S105 degree 2 poles (3.9591, 1.4513) (3.7646, 1.4513) (3.4729, 1.5133) (3.3744, 1.5826) knots 0 0 0 1 2 2 2
  spline S106 degree 2 poles (3.3744, 1.5826) (3.2772, 1.6507) (3.1775, 1.8707) (3.1775, 2.0287) knots 0 0 0 1 2 2 2
  spline S107 degree 2 poles (3.1775, 2.0287) (3.1775, 2.188) (3.2772, 2.4068) (3.3768, 2.4761) knots 0 0 0 1 2 2 2
  spline S108 degree 2 poles (3.3768, 2.4761) (3.4753, 2.5453) (3.7646, 2.6073) (3.9591, 2.6073) knots 0 0 0 1 2 2 2
  spline S109 degree 2 poles (3.9591, 2.6073) (4.1584, 2.6073) (4.4404, 2.5453) (4.5426, 2.4748) knots 0 0 0 1 2 2 2
  spline S110 degree 2 poles (4.5426, 2.4748) (4.6422, 2.4043) (4.7395, 2.1819) (4.7395, 2.0287) knots 0 0 0 1 2 2 2
  spline S111 degree 2 poles (4.7395, 2.0287) (4.7395, 1.8671) (4.6374, 1.6507) (4.5365, 1.5814) knots 0 0 0 1 2 2 2
  spline S112 degree 2 poles (4.5365, 1.5814) (4.438, 1.5133) (4.1475, 1.4513) (3.9591, 1.4513) knots 0 0 0 1 2 2 2
  spline S113 degree 2 poles (3.9591, 1.8294) (4.2375, 1.8294) (4.4623, 1.9206) (4.4623, 2.0287) knots 0 0 0 1 2 2 2
  spline S114 degree 2 poles (4.4623, 2.0287) (4.4623, 2.1369) (4.2375, 2.2293) (3.9579, 2.2293) knots 0 0 0 1 2 2 2
  spline S115 degree 2 poles (3.9579, 2.2293) (3.6832, 2.2293) (3.4546, 2.1369) (3.4546, 2.0287) knots 0 0 0 1 2 2 2
  spline S116 degree 2 poles (3.4546, 2.0287) (3.4546, 1.9218) (3.6832, 1.8294) (3.9591, 1.8294) knots 0 0 0 1 2 2 2
  spline S117 degree 2 poles (3.626, 0.1215) (3.53, 0.1215) (3.3635, 0.2018) (3.3027, 0.2783) knots 0 0 0 1 2 2 2
  spline S118 degree 2 poles (3.3027, 0.2783) (3.2419, 0.3549) (3.1738, 0.5749) (3.1738, 0.7171) knots 0 0 0 1 2 2 2
  spline S119 degree 2 poles (3.1738, 0.7171) (3.1738, 0.8691) (3.2431, 1.0964) (3.3027, 1.1693) knots 0 0 0 1 2 2 2
  spline S120 degree 2 poles (3.3027, 1.1693) (3.3622, 1.2411) (3.5239, 1.3091) (3.6139, 1.3091) knots 0 0 0 1 2 2 2
  spline S121 degree 2 poles (3.6139, 1.3091) (3.7427, 1.3091) (3.9141, 1.1669) (3.9712, 1.032) knots 0 0 0 1 2 2 2
  line L159 (3.9712, 1.032) -> (3.9773, 1.032)
  spline S122 degree 2 poles (3.9773, 1.032) (4.0417, 1.1645) (4.2253, 1.269) (4.3383, 1.269) knots 0 0 0 1 2 2 2
  spline S123 degree 2 poles (4.3383, 1.269) (4.421, 1.269) (4.5657, 1.1961) (4.6228, 1.1244) knots 0 0 0 1 2 2 2
  spline S124 degree 2 poles (4.6228, 1.1244) (4.6775, 1.0551) (4.7431, 0.8448) (4.7431, 0.7135) knots 0 0 0 1 2 2 2
  spline S125 degree 2 poles (4.7431, 0.7135) (4.7431, 0.5749) (4.6836, 0.3683) (4.6349, 0.3014) knots 0 0 0 1 2 2 2
  spline S126 degree 2 poles (4.6349, 0.3014) (4.5863, 0.2334) (4.4453, 0.1604) (4.3639, 0.1604) knots 0 0 0 1 2 2 2
  spline S127 degree 2 poles (4.3639, 0.1604) (4.2569, 0.1604) (4.0855, 0.2844) (4.0259, 0.412) knots 0 0 0 1 2 2 2
  line L160 (4.0259, 0.412) -> (4.0211, 0.412)
  spline S128 degree 2 poles (4.0211, 0.412) (3.9603, 0.2625) (3.7634, 0.1215) (3.626, 0.1215) knots 0 0 0 1 2 2 2
  spline S129 degree 2 poles (3.6102, 0.4935) (3.6844, 0.4935) (3.7622, 0.5567) (3.812, 0.6588) knots 0 0 0 1 2 2 2
  spline S130 degree 2 poles (3.812, 0.6588) (3.8254, 0.688) (3.8679, 0.7986) (3.8862, 0.8411) knots 0 0 0 1 2 2 2
  spline S131 degree 2 poles (3.8862, 0.8411) (3.8473, 0.88) (3.7306, 0.942) (3.6613, 0.942) knots 0 0 0 1 2 2 2
  spline S132 degree 2 poles (3.6613, 0.942) (3.5567, 0.942) (3.4315, 0.8083) (3.4315, 0.7001) knots 0 0 0 1 2 2 2
  spline S133 degree 2 poles (3.4315, 0.7001) (3.4315, 0.6697) (3.451, 0.5944) (3.4704, 0.5652) knots 0 0 0 1 2 2 2
  spline S134 degree 2 poles (3.4704, 0.5652) (3.4935, 0.5324) (3.5567, 0.4935) (3.6102, 0.4935) knots 0 0 0 1 2 2 2
  spline S135 degree 2 poles (4.3201, 0.5263) (4.3967, 0.5263) (4.4879, 0.6272) (4.4879, 0.7135) knots 0 0 0 1 2 2 2
  spline S136 degree 2 poles (4.4879, 0.7135) (4.4879, 0.7962) (4.4052, 0.8971) (4.3444, 0.8971) knots 0 0 0 1 2 2 2
  spline S137 degree 2 poles (4.3444, 0.8971) (4.2849, 0.8971) (4.2107, 0.8363) (4.1803, 0.7718) knots 0 0 0 1 2 2 2
  spline S138 degree 2 poles (4.1803, 0.7718) (4.1657, 0.7439) (4.1353, 0.6661) (4.111, 0.6017) knots 0 0 0 1 2 2 2
  spline S139 degree 2 poles (4.111, 0.6017) (4.1621, 0.5628) (4.2581, 0.5263) (4.3201, 0.5263) knots 0 0 0 1 2 2 2
  line L161 (3.7318, -0.7196) -> (3.7318, -0.0523)
  line L162 (3.7318, -0.0523) -> (4.0114, -0.0523)
  line L163 (4.0114, -0.0523) -> (4.0114, -0.7196)
  line L164 (4.0114, -0.7196) -> (3.7318, -0.7196)
  line L165 (3.2091, -2.0191) -> (3.2091, -1.0284)
  line L166 (3.2091, -1.0284) -> (3.4704, -1.0284)
  line L167 (3.4704, -1.0284) -> (3.4704, -1.3444)
  line L168 (3.4704, -1.3444) -> (4.2642, -1.3444)
  line L169 (4.2642, -1.3444) -> (4.2642, -1.0284)
  line L170 (4.2642, -1.0284) -> (4.5085, -1.0284)
  spline S140 degree 2 poles (4.5085, -1.0284) (4.5085, -1.0977) (4.5268, -1.235) (4.5462, -1.2764) knots 0 0 0 1 2 2 2
  spline S141 degree 2 poles (4.5462, -1.2764) (4.5705, -1.3238) (4.652, -1.3773) (4.7127, -1.3821) knots 0 0 0 1 2 2 2
  line L171 (4.7127, -1.3821) -> (4.7127, -1.7103)
  line L172 (4.7127, -1.7103) -> (3.4704, -1.7103)
  line L173 (3.4704, -1.7103) -> (3.4704, -2.0191)
  line L174 (3.4704, -2.0191) -> (3.2091, -2.0191)
  spline S142 degree 2 poles (3.7172, -3.3659) (3.5993, -3.3659) (3.3999, -3.2857) (3.3282, -3.2067) knots 0 0 0 1 2 2 2
  spline S143 degree 2 poles (3.3282, -3.2067) (3.2565, -3.1277) (3.1775, -2.9113) (3.1775, -2.7533) knots 0 0 0 1 2 2 2
  spline S144 degree 2 poles (3.1775, -2.7533) (3.1787, -2.5855) (3.2334, -2.3448) (3.2687, -2.2658) knots 0 0 0 1 2 2 2
  line L175 (3.2687, -2.2658) -> (3.5956, -2.2658)
  line L176 (3.5956, -2.2658) -> (3.5956, -2.2999)
  spline S145 degree 2 poles (3.5956, -2.2999) (3.5798, -2.329) (3.5385, -2.3995) (3.5166, -2.4567) knots 0 0 0 1 2 2 2
  spline S146 degree 2 poles (3.5166, -2.4567) (3.496, -2.5102) (3.468, -2.6208) (3.468, -2.6876) knots 0 0 0 1 2 2 2
  spline S147 degree 2 poles (3.468, -2.6876) (3.468, -2.746) (3.4972, -2.8821) (3.5361, -2.9235) knots 0 0 0 1 2 2 2
  spline S148 degree 2 poles (3.5361, -2.9235) (3.5665, -2.9538) (3.6406, -2.9879) (3.7026, -2.9879) knots 0 0 0 1 2 2 2
  spline S149 degree 2 poles (3.7026, -2.9879) (3.7561, -2.9879) (3.8315, -2.9441) (3.8546, -2.9089) knots 0 0 0 1 2 2 2
  spline S150 degree 2 poles (3.8546, -2.9089) (3.8886, -2.8578) (3.908, -2.7119) (3.908, -2.6597) knots 0 0 0 1 2 2 2
  spline S151 degree 2 poles (3.908, -2.6597) (3.908, -2.577) (3.8813, -2.4202) (3.8667, -2.3631) knots 0 0 0 1 2 2 2
  line L177 (3.8667, -2.3631) -> (3.8667, -2.3303)
  line L178 (3.8667, -2.3303) -> (4.7091, -2.3303)
  line L179 (4.7091, -2.3303) -> (4.7091, -3.3246)
  line L180 (4.7091, -3.3246) -> (4.4259, -3.3246)
  line L181 (4.4259, -3.3246) -> (4.4259, -2.6864)
  line L182 (4.4259, -2.6864) -> (4.1767, -2.6864)
  spline S152 degree 2 poles (4.1767, -2.6864) (4.1791, -2.7168) (4.1815, -2.8007) (4.1815, -2.8238) knots 0 0 0 1 2 2 2
  spline S153 degree 2 poles (4.1815, -2.8238) (4.1815, -2.932) (4.1378, -3.1143) (4.0928, -3.186) knots 0 0 0 1 2 2 2
  spline S154 degree 2 poles (4.0928, -3.186) (4.0369, -3.2711) (3.8509, -3.3659) (3.7172, -3.3659) knots 0 0 0 1 2 2 2
  spline S155 degree 2 poles (3.9591, -4.6945) (3.7646, -4.6945) (3.4729, -4.6325) (3.3744, -4.5632) knots 0 0 0 1 2 2 2
  spline S156 degree 2 poles (3.3744, -4.5632) (3.2772, -4.4952) (3.1775, -4.2752) (3.1775, -4.1171) knots 0 0 0 1 2 2 2
  spline S157 degree 2 poles (3.1775, -4.1171) (3.1775, -3.9579) (3.2772, -3.7391) (3.3768, -3.6698) knots 0 0 0 1 2 2 2
  spline S158 degree 2 poles (3.3768, -3.6698) (3.4753, -3.6005) (3.7646, -3.5385) (3.9591, -3.5385) knots 0 0 0 1 2 2 2
  spline S159 degree 2 poles (3.9591, -3.5385) (4.1584, -3.5385) (4.4404, -3.6005) (4.5426, -3.671) knots 0 0 0 1 2 2 2
  spline S160 degree 2 poles (4.5426, -3.671) (4.6422, -3.7415) (4.7395, -3.964) (4.7395, -4.1171) knots 0 0 0 1 2 2 2
  spline S161 degree 2 poles (4.7395, -4.1171) (4.7395, -4.2788) (4.6374, -4.4952) (4.5365, -4.5645) knots 0 0 0 1 2 2 2
  spline S162 degree 2 poles (4.5365, -4.5645) (4.438, -4.6325) (4.1475, -4.6945) (3.9591, -4.6945) knots 0 0 0 1 2 2 2
  spline S163 degree 2 poles (3.9591, -4.3165) (4.2375, -4.3165) (4.4623, -4.2253) (4.4623, -4.1171) knots 0 0 0 1 2 2 2
  spline S164 degree 2 poles (4.4623, -4.1171) (4.4623, -4.0089) (4.2375, -3.9166) (3.9579, -3.9166) knots 0 0 0 1 2 2 2
  spline S165 degree 2 poles (3.9579, -3.9166) (3.6832, -3.9166) (3.4546, -4.0089) (3.4546, -4.1171) knots 0 0 0 1 2 2 2
  spline S166 degree 2 poles (3.4546, -4.1171) (3.4546, -4.2241) (3.6832, -4.3165) (3.9591, -4.3165) knots 0 0 0 1 2 2 2
  line L183 (3.2091, -5.2172) -> (4.4234, -5.2172)
  line L184 (4.4234, -5.2172) -> (4.4234, -4.7735)
  line L185 (4.4234, -4.7735) -> (4.7091, -4.7735)
  line L186 (4.7091, -4.7735) -> (4.7091, -6.0377)
  line L187 (4.7091, -6.0377) -> (4.4234, -6.0377)
  line L188 (4.4234, -6.0377) -> (4.4234, -5.594)
  line L189 (4.4234, -5.594) -> (3.2091, -5.594)
  line L190 (3.2091, -5.594) -> (3.2091, -5.2172)
  spline S167 degree 2 poles (3.1851, -7.1992) (3.1851, -7.0936) (3.2264, -7.012) knots 0 0 0 1 1 1
  line L191 (3.2264, -7.012) -> (2.9653, -6.8652)
  line L192 (2.9653, -6.8652) -> (3.0267, -6.752)
  line L193 (3.0267, -6.752) -> (3.2916, -6.9007)
  spline S168 degree 2 poles (3.2916, -6.9007) (3.3569, -6.8115) (3.5719, -6.7078) (3.6918, -6.7078) knots 0 0 0 1 2 2 2
  spline S169 degree 2 poles (3.6918, -6.7078) (3.9077, -6.7078) (4.0517, -6.845) knots 0 0 0 1 1 1
  spline S170 degree 2 poles (4.0517, -6.845) (4.1976, -6.9842) (4.1976, -7.1992) knots 0 0 0 1 1 1
  spline S171 degree 2 poles (4.1976, -7.1992) (4.1976, -7.3038) (4.1563, -7.3863) knots 0 0 0 1 1 1
  line L194 (4.1563, -7.3863) -> (4.4183, -7.5331)
  line L195 (4.4183, -7.5331) -> (4.3559, -7.6454)
  line L196 (4.3559, -7.6454) -> (4.0901, -7.4976)
  spline S172 degree 2 poles (4.0901, -7.4976) (4.0239, -7.5869) (3.8108, -7.6925) (3.6928, -7.6925) knots 0 0 0 1 2 2 2
  spline S173 degree 2 poles (3.6928, -7.6925) (3.4768, -7.6925) (3.3319, -7.5552) knots 0 0 0 1 1 1
  spline S174 degree 2 poles (3.3319, -7.5552) (3.1851, -7.4151) (3.1851, -7.1992) knots 0 0 0 1 1 1
  line L197 (3.9778, -7.4333) -> (3.3425, -7.0735)
  spline S175 degree 2 poles (3.3425, -7.0735) (3.3214, -7.1282) (3.3214, -7.1992) knots 0 0 0 1 1 1
  spline S176 degree 2 poles (3.3214, -7.1992) (3.3214, -7.3575) (3.4279, -7.4583) knots 0 0 0 1 1 1
  spline S177 degree 2 poles (3.4279, -7.4583) (3.5325, -7.5581) (3.6928, -7.5581) knots 0 0 0 1 1 1
  spline S178 degree 2 poles (3.6928, -7.5581) (3.8703, -7.5581) (3.9778, -7.4333) knots 0 0 0 1 1 1
  spline S179 degree 2 poles (4.0613, -7.1992) (4.0613, -7.0427) (3.8502, -6.8422) (3.6918, -6.8422) knots 0 0 0 1 2 2 2
  spline S180 degree 2 poles (3.6918, -6.8422) (3.5114, -6.8422) (3.4049, -6.966) knots 0 0 0 1 1 1
  line L198 (3.4049, -6.966) -> (4.0402, -7.3249)
  spline S181 degree 2 poles (4.0402, -7.3249) (4.0613, -7.2692) (4.0613, -7.1992) knots 0 0 0 1 1 1
  spline S182 degree 2 poles (3.1896, -8.6934) (3.1896, -8.4681) (3.4619, -8.2039) (3.7083, -8.2039) knots 0 0 0 1 2 2 2
  spline S183 degree 2 poles (3.7083, -8.2039) (3.9457, -8.2039) (4.2285, -8.4689) (4.2285, -8.6942) knots 0 0 0 1 2 2 2
  spline S184 degree 2 poles (4.2285, -8.6942) (4.2285, -8.7534) (4.2148, -8.849) (4.2034, -8.8927) knots 0 0 0 1 2 2 2
  spline S185 degree 2 poles (4.2034, -8.8927) (4.1929, -8.9268) (4.158, -9.007) (4.1451, -9.0321) knots 0 0 0 1 2 2 2
  line L199 (4.1451, -9.0321) -> (3.9068, -9.0321)
  line L200 (3.9068, -9.0321) -> (3.9068, -9.007)
  spline S186 degree 2 poles (3.9068, -9.007) (3.923, -8.9884) (3.9684, -8.9333) (3.9895, -8.8984) knots 0 0 0 1 2 2 2
  spline S187 degree 2 poles (3.9895, -8.8984) (4.0114, -8.8636) (4.0413, -8.7801) (4.0413, -8.7339) knots 0 0 0 1 2 2 2
  spline S188 degree 2 poles (4.0413, -8.7339) (4.0413, -8.6796) (4.0073, -8.5897) (3.9644, -8.5483) knots 0 0 0 1 2 2 2
  spline S189 degree 2 poles (3.9644, -8.5483) (3.9263, -8.5111) (3.7958, -8.4633) (3.7075, -8.4633) knots 0 0 0 1 2 2 2
  spline S190 degree 2 poles (3.7075, -8.4633) (3.6143, -8.4633) (3.487, -8.5127) (3.4481, -8.5532) knots 0 0 0 1 2 2 2
  spline S191 degree 2 poles (3.4481, -8.5532) (3.4101, -8.5921) (3.3768, -8.6877) (3.3768, -8.7355) knots 0 0 0 1 2 2 2
  spline S192 degree 2 poles (3.3768, -8.7355) (3.3768, -8.785) (3.4101, -8.8749) (3.4303, -8.9057) knots 0 0 0 1 2 2 2
  spline S193 degree 2 poles (3.4303, -8.9057) (3.4506, -8.9398) (3.4935, -8.9908) (3.5105, -9.0094) knots 0 0 0 1 2 2 2
  line L201 (3.5105, -9.0094) -> (3.5105, -9.0321)
  line L202 (3.5105, -9.0321) -> (3.2755, -9.0321)
  spline S194 degree 2 poles (3.2755, -9.0321) (3.2626, -9.0046) (3.2302, -8.9325) (3.2188, -8.8936) knots 0 0 0 1 2 2 2
  spline S195 degree 2 poles (3.2188, -8.8936) (3.2042, -8.8466) (3.1896, -8.7647) (3.1896, -8.6934) knots 0 0 0 1 2 2 2
  line L203 (3.2091, -9.1804) -> (4.2091, -9.1804)
  line L204 (4.2091, -9.1804) -> (4.2091, -9.8563)
  line L205 (4.2091, -9.8563) -> (4.0187, -9.8563)
  line L206 (4.0187, -9.8563) -> (4.0187, -9.43)
  line L207 (4.0187, -9.43) -> (3.8428, -9.43)
  line L208 (3.8428, -9.43) -> (3.8428, -9.8231)
  line L209 (3.8428, -9.8231) -> (3.6524, -9.8231)
  line L210 (3.6524, -9.8231) -> (3.6524, -9.43)
  line L211 (3.6524, -9.43) -> (3.3995, -9.43)
  line L212 (3.3995, -9.43) -> (3.3995, -9.8563)
  line L213 (3.3995, -9.8563) -> (3.2091, -9.8563)
  line L214 (3.2091, -9.8563) -> (3.2091, -9.1804)
  line L215 (3.2091, -11.353) -> (3.2091, -11.0475)
  line L216 (3.2091, -11.0475) -> (3.5762, -10.7696)
  line L217 (3.5762, -10.7696) -> (3.5762, -10.6788)
  line L218 (3.5762, -10.6788) -> (3.2091, -10.6788)
  line L219 (3.2091, -10.6788) -> (3.2091, -10.4292)
  line L220 (3.2091, -10.4292) -> (4.2091, -10.4292)
  line L221 (4.2091, -10.4292) -> (4.2091, -10.8312)
  spline S196 degree 2 poles (4.2091, -10.8312) (4.2091, -10.9146) (4.188, -11.0378) (4.1556, -11.0905) knots 0 0 0 1 2 2 2
  spline S197 degree 2 poles (4.1556, -11.0905) (4.1216, -11.144) (4.0154, -11.2072) (3.9344, -11.2072) knots 0 0 0 1 2 2 2
  spline S198 degree 2 poles (3.9344, -11.2072) (3.8201, -11.2072) (3.6767, -11.1034) (3.6345, -11.0167) knots 0 0 0 1 2 2 2
  line L222 (3.6345, -11.0167) -> (3.2091, -11.353)
  spline S199 degree 2 poles (3.9028, -10.9495) (3.9409, -10.9495) (3.9951, -10.9203) (4.0097, -10.8871) knots 0 0 0 1 2 2 2
  spline S200 degree 2 poles (4.0097, -10.8871) (4.0195, -10.8636) (4.0251, -10.806) (4.0251, -10.7631) knots 0 0 0 1 2 2 2
  line L223 (4.0251, -10.7631) -> (4.0251, -10.6788)
  line L224 (4.0251, -10.6788) -> (3.7561, -10.6788)
  line L225 (3.7561, -10.6788) -> (3.7561, -10.7509)
  spline S201 degree 2 poles (3.7561, -10.7509) (3.7561, -10.8028) (3.7691, -10.8765) (3.7893, -10.9017) knots 0 0 0 1 2 2 2
  spline S202 degree 2 poles (3.7893, -10.9017) (3.8088, -10.926) (3.8606, -10.9495) (3.9028, -10.9495) knots 0 0 0 1 2 2 2
  spline S203 degree 2 poles (3.5859, -12.1375) (3.3995, -12.1375) (3.1856, -11.9341) (3.1856, -11.7485) knots 0 0 0 1 2 2 2
  spline S204 degree 2 poles (3.1856, -11.7485) (3.1856, -11.5637) (3.3995, -11.3587) (3.5859, -11.3587) knots 0 0 0 1 2 2 2
  spline S205 degree 2 poles (3.5859, -11.3587) (3.7739, -11.3587) (3.987, -11.5637) (3.987, -11.7485) knots 0 0 0 1 2 2 2
  spline S206 degree 2 poles (3.987, -11.7485) (3.987, -11.9333) (3.7731, -12.1375) (3.5859, -12.1375) knots 0 0 0 1 2 2 2
  spline S207 degree 2 poles (3.5843, -11.8968) (3.6516, -11.8968) (3.7415, -11.8749) (3.7682, -11.8555) knots 0 0 0 1 2 2 2
  spline S208 degree 2 poles (3.7682, -11.8555) (3.7966, -11.8344) (3.8185, -11.7817) (3.8185, -11.7485) knots 0 0 0 1 2 2 2
  spline S209 degree 2 poles (3.8185, -11.7485) (3.8185, -11.7161) (3.799, -11.665) (3.7715, -11.644) knots 0 0 0 1 2 2 2
  spline S210 degree 2 poles (3.7715, -11.644) (3.7456, -11.6237) (3.654, -11.5994) (3.5843, -11.5994) knots 0 0 0 1 2 2 2
  spline S211 degree 2 poles (3.5843, -11.5994) (3.5154, -11.5994) (3.4303, -11.6221) (3.4044, -11.6407) knots 0 0 0 1 2 2 2
  spline S212 degree 2 poles (3.4044, -11.6407) (3.3785, -11.6594) (3.3541, -11.7161) (3.3541, -11.7501) knots 0 0 0 1 2 2 2
  spline S213 degree 2 poles (3.3541, -11.7501) (3.3541, -11.7785) (3.3785, -11.8368) (3.4028, -11.8547) knots 0 0 0 1 2 2 2
  spline S214 degree 2 poles (3.4028, -11.8547) (3.4311, -11.8749) (3.513, -11.8968) (3.5843, -11.8968) knots 0 0 0 1 2 2 2
  line L226 (3.2091, -13.1197) -> (3.2091, -12.8684)
  line L227 (3.2091, -12.8684) -> (3.6524, -12.8684)
  line L228 (3.6524, -12.8684) -> (3.6524, -12.5273)
  line L229 (3.6524, -12.5273) -> (3.2091, -12.5273)
  line L230 (3.2091, -12.5273) -> (3.2091, -12.2761)
  line L231 (3.2091, -12.2761) -> (4.2091, -12.2761)
  line L232 (4.2091, -12.2761) -> (4.2091, -12.5273)
  line L233 (4.2091, -12.5273) -> (3.8428, -12.5273)
  line L234 (3.8428, -12.5273) -> (3.8428, -12.8684)
  line L235 (3.8428, -12.8684) -> (4.2091, -12.8684)
  line L236 (4.2091, -12.8684) -> (4.2091, -13.1197)
  line L237 (4.2091, -13.1197) -> (3.2091, -13.1197)
  spline S215 degree 2 poles (3.1913, -13.6359) (3.1913, -13.5208) (3.2358, -13.3474) (3.2682, -13.2728) knots 0 0 0 1 2 2 2
  line L238 (3.2682, -13.2728) -> (3.5065, -13.2728)
  line L239 (3.5065, -13.2728) -> (3.5065, -13.2955)
  spline S216 degree 2 poles (3.5065, -13.2955) (3.4425, -13.3709) (3.3736, -13.5516) (3.3736, -13.6367) knots 0 0 0 1 2 2 2
  spline S217 degree 2 poles (3.3736, -13.6367) (3.3736, -13.6586) (3.3833, -13.7291) (3.393, -13.7501) knots 0 0 0 1 2 2 2
  spline S218 degree 2 poles (3.393, -13.7501) (3.4044, -13.7761) (3.4457, -13.8125) (3.4789, -13.8125) knots 0 0 0 1 2 2 2
  spline S219 degree 2 poles (3.4789, -13.8125) (3.517, -13.8125) (3.564, -13.7534) (3.5746, -13.7128) knots 0 0 0 1 2 2 2
  spline S220 degree 2 poles (3.5746, -13.7128) (3.5883, -13.6618) (3.6118, -13.5459) (3.6297, -13.4949) knots 0 0 0 1 2 2 2
  spline S221 degree 2 poles (3.6297, -13.4949) (3.6702, -13.379) (3.8088, -13.2785) (3.9125, -13.2785) knots 0 0 0 1 2 2 2
  spline S222 degree 2 poles (3.9125, -13.2785) (4.0527, -13.2785) (4.2269, -13.5159) (4.2269, -13.6942) knots 0 0 0 1 2 2 2
  spline S223 degree 2 poles (4.2269, -13.6942) (4.2269, -13.7833) (4.1904, -13.96) (4.1597, -14.0297) knots 0 0 0 1 2 2 2
  line L240 (4.1597, -14.0297) -> (3.9311, -14.0297)
  line L241 (3.9311, -14.0297) -> (3.9311, -14.0078)
  spline S224 degree 2 poles (3.9311, -14.0078) (3.9789, -13.9519) (4.0446, -13.7915) (4.0446, -13.7072) knots 0 0 0 1 2 2 2
  spline S225 degree 2 poles (4.0446, -13.7072) (4.0446, -13.6739) (4.0349, -13.6221) (4.0219, -13.5929) knots 0 0 0 1 2 2 2
  spline S226 degree 2 poles (4.0219, -13.5929) (4.0114, -13.5694) (3.9692, -13.5354) (3.9433, -13.5354) knots 0 0 0 1 2 2 2
  spline S227 degree 2 poles (3.9433, -13.5354) (3.9044, -13.5354) (3.8598, -13.5897) (3.842, -13.6675) knots 0 0 0 1 2 2 2
  spline S228 degree 2 poles (3.842, -13.6675) (3.8306, -13.7177) (3.8088, -13.8109) (3.7901, -13.8644) knots 0 0 0 1 2 2 2
  spline S229 degree 2 poles (3.7901, -13.8644) (3.752, -13.9681) (3.6256, -14.0694) (3.5219, -14.0694) knots 0 0 0 1 2 2 2
  spline S230 degree 2 poles (3.5219, -14.0694) (3.3728, -14.0694) (3.1913, -13.8352) (3.1913, -13.6359) knots 0 0 0 1 2 2 2
  point P0 (0, 0)
  dimension "d0" = 50
  dimension "d1" = 3.17
  dimension "d2" = 8
  dimension "d3" = 16
  dimension "d6" = 360
  dimension "d10" = 2
  dimension "d11" = 2
  dimension "d12" = 2
  dimension "d13" = 2
  dimension "d86" = 12
  constraints: 8 end point, 2 parallel, 1 horizontal, 1 perpendicular, 2 other
emboss "Emboss1" sketch "Sketch5" operation add depth 0.01 direction (-0.9488702, 0, -0.3156666) wrap yes faces at (-24.6763, 6.7667, 4.0103) contours S0 S1 S2 S3 L8 L9 S4 S5 S6 S7 S8 S9 L10 L11 L12 L13 L14 | L15 L16 L17 L18 L19 L20 L21 L22 L23 L24 L25 L26 | L27 L28 L29 L30 L31 L32 L33 L34 L35 L36 L37 L38 L39 | S10 S11 L40 L41 L42 S12 S13 S14 L43 S15 | L50 L51 L52 L53 L54 L55 L56 L57 | L61 L62 L63 L64 L65 L66 | S24 S25 L67 L68 L69 S26 S27 S28 L70 S29 | L77 L78 L79 L80 L81 L82 | L83 L84 L85 L86 L87 L88 L89 L90 L91 L92 L93 L94 L95 | S38 S39 S40 S41 | L96 L97 L98 L99 L100 L101 L102 L103 | S50 S51 S52 S53 | L104 L105 L106 L107 L108 L109 L110 S62 S63 S64 L111 | S69 S70 S71 S72 L115 L116 S73 S74 S75 S76 S77 S78 L117 L118 L119 L120 L121 | S79 S80 L122 L123 L124 S81 S82 S83 L125 S84 | L132 L133 L134 L135 L136 L137 L138 L139 L140 L141 L142 L143 L144 | L145 L146 L147 L148 L149 L150 L151 L152 L153 L154 L155 | S93 S94 S95 S96 S97 S98 S99 S100 | S105 S106 S107 S108 S109 S110 S111 S112 | S117 S118 S119 S120 S121 L159 S122 S123 S124 S125 S126 S127 L160 S128 | L161 L162 L163 L164 | L165 L166 L167 L168 L169 L170 S140 S141 L171 L172 L173 L174 | S142 S143 S144 L175 L176 S145 S146 S147 S148 S149 S150 S151 L177 L178 L179 L180 L181 L182 S152 S153 S154 | S155 S156 S157 S158 S159 S160 S161 S162 | L183 L184 L185 L186 L187 L188 L189 L190 | S167 L191 L192 L193 S168 S169 S170 S171 L194 L195 L196 S172 S173 S174 | S182 S183 S184 S185 L199 L200 S186 S187 S188 S189 S190 S191 S192 S193 L201 L202 S194 S195 | L203 L204 L205 L206 L207 L208 L209 L210 L211 L212 L213 L214 | L215 L216 L217 L218 L219 L220 L221 S196 S197 S198 L222 | S203 S204 S205 S206 | L226 L227 L228 L229 L230 L231 L232 L233 L234 L235 L236 L237 | S215 L238 L239 S216 S217 S218 S219 S220 S221 S222 S223 L240 L241 S224 S225 S226 S227 S228 S229 S230
ref_plane "Work Plane5" through (5.0265, 0, 24.4895) normal (0.2010598, 0, 0.979579) x (0, 1, 0)
ref_plane "Work Plane4" through (0, 0, 0) normal (-0.2010598, 0, -0.979579) x (0, 1, 0)